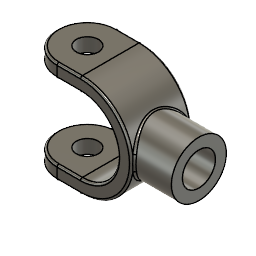
Assembly of U-V Joint (Autodesk Fusion 360 archive; units mm, degrees)
design "Arm-1"
Autodesk Fusion 360 part; units mm, degrees
sketch "Sketch1" plane through (0, 0, 0) normal (0, 0, 1) x (1, 0, 0)
  line L0 (13.5, -13.5) -> (28, -13.5)
  arc A0 (28, -13.5) -> (28, 13.5) centre (28, 0) ccw
  line L1 (28, 13.5) -> (13.5, 13.5)
  line L2 (13.5, -18.5) -> (28, -18.5)
  arc A1 (28, -18.5) -> (28, 18.5) centre (28, 0) ccw
  line L3 (28, 18.5) -> (13.5, 18.5)
  line L4 (13.5, -13.5) -> (13.5, -18.5)
  line L5 (13.5, 13.5) -> (13.5, 18.5)
  line L6 (13.5, 18.5) -> (8.5, 18.5)
  line L7 (8.5, 18.5) -> (8.5, 13.5)
  line L8 (8.5, 13.5) -> (13.5, 13.5)
  line L9 (13.5, 13.5) -> (13.5, 18.5)
  line L10 (13.5, -13.5) -> (8.5, -13.5)
  line L11 (8.5, -13.5) -> (8.5, -18.5)
  line L12 (8.5, -18.5) -> (13.5, -18.5)
  line L13 (13.5, -18.5) -> (13.5, -13.5)
  dimension "d1" = 28
  dimension "d2" = 27
  dimension "d16" = 5
  dimension "d17" = 5
  dimension "d18" = 5
  constraint tangent L0 A0
  constraint tangent A0 L1
  constraint parallel L0 L1
  constraint concentric A0 A1
  constraint tangent A1 L3
  constraint tangent L2 A1
  constraint horizontal L6
  constraint vertical L7
  constraint horizontal L8
  constraint vertical L9
  constraint horizontal L10
  constraint vertical L11
  constraint horizontal L12
  constraint vertical L13
  measures "d1" distance of origin A0.centre
  measures "d2" diameter of A0
  measures "d16" distance of L3.end L6.end
  measures "d17" distance of L3.end L1.end
  measures "d18" distance of L0.start L2.start
ref_plane "WorkPlane1" through (43, 0, 0) normal (1, 0, 0) x (0, 1, 0)
sketch "Sketch2" plane through (43, 0, 0) normal (1, 0, 0) x (0, 0, -1)
  circle A0 centre (0, 0) radius 10
  circle A1 centre (0, 0) radius 6
  constraint coincident A0.centre A1.centre
  constraint concentric A0 A1
extrude "Extrude4" add sketch "Sketch1" along normal mid plane 22
sketch "Sketch4" plane through (43, 0, 0) normal (1, 0, 0) x (0, 0, -1)
  circle A0 centre (0, 0) radius 10
  circle A1 centre (0, 0) radius 6
  constraint coincident A0.centre A1.centre
extrude "Extrude5" add sketch "Sketch4" along normal blind 17
sketch "Sketch5" plane through (0, 18.5, 0) normal (0, 1, 0) x (-1, 0, 0)
  line L0 (-8.5, -11) -> (-8.5, 11)
  line L1 (-8.5, 11) -> (-28, 11)
  line L2 (-28, 11) -> (-28, -11)
  line L3 (-28, -11) -> (-8.5, -11)
  line L4 (-8.5, 0) -> (-19.5, 0)
  circle A0 centre (-19.5, 0) radius 11
  circle A1 centre (-19.5, 0) radius 4
  dimension "d23" = 11
  dimension "d24" = 8
  constraint midpoint L0 L4.start
  constraint perpendicular L0 L4
  constraint coincident L4.end A0.centre
  constraint tangent L1 A0
  constraint concentric A0 A1
  measures "d23" distance of L4.start L4.end
  measures "d24" diameter of A1
extrude "Extrude6" cut sketch "Sketch5" against normal blind 43 contours L0 L3 A0 | L0 L1 A0 | A1
fillet "Fillet2" radius 0.7 17 edges at (23.75, 18.5, 11) (46.5, 0, 11) (23.75, -18.5, 11) (8.5, -18.5, 0) (23.75, -18.5, -11) (46.5, 0, -11) (23.75, 18.5, -11) (8.5, 18.5, 0) (43.5644, -10, 0) (8.5, -13.5, 0) (23.75, -13.5, -11) (41.5, 0, -11) (23.75, 13.5, -11) (8.5, 13.5, 0) (23.75, 13.5, 11) (41.5, 0, 11) (23.75, -13.5, 11)

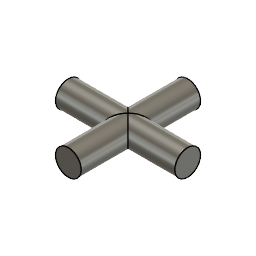
design "U-V Center"
Autodesk Fusion 360 part; units mm, degrees
sketch "Sketch1" plane through (0, 0, 0) normal (0, 1, 0) x (1, 0, 0)
  line L0 (0, 0) -> (0, 18.5)
  line L1 (0, 0) -> (0, -18.5)
  line L2 (0, 0) -> (18.5, 0)
  line L3 (0, 0) -> (-18.5, 0)
  dimension "d1" = 18.5
  dimension "d2" = 18.5
  dimension "d3" = 18.5
  dimension "d4" = 18.5
  constraint coincident L0.start L1.start
  constraint vertical L0
  constraint parallel L0 L1
  constraint perpendicular L0 L2
  constraint perpendicular L0 L3
  measures "d1" distance of L0.start L0.end
  measures "d2" distance of L0.start L1.end
  measures "d3" distance of L0.start L2.end
  measures "d4" distance of L0.start L3.end
pipe "Pipe1" add diameter 8 path "Sketch1" along L3 L2
pipe "Pipe2" add diameter 8 path "Sketch1" along L1 L0
equation "d1 = ( 37 / 2 ) * 1 mm"
equation "d2 = ( 37 / 2 ) * 1 mm"
equation "d3 = ( 37 / 2 ) * 1 mm"
equation "d4 = ( 37 / 2 ) * 1 mm"
